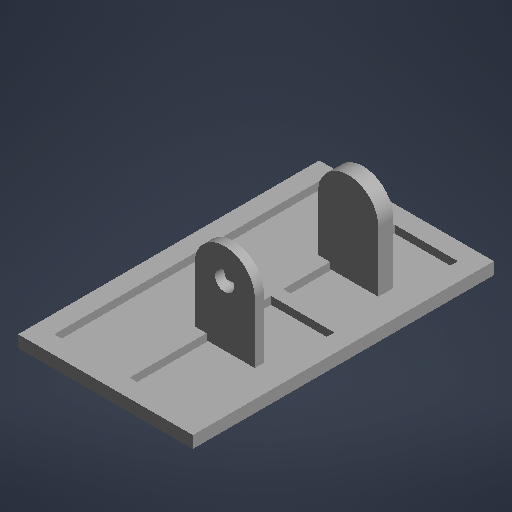
# Autodesk Inventor part: R2_pie_der
Saved by Autodesk Inventor 2027 (Build 310192060, 192F)
## iProperties
Part Number: R2_pie_der
Material: Genérico
Document SubType Name: Modelado
Designer: rodri
Appearance: Por defecto
Author: rodri
Autodesk Inventor part; units mm, degrees
ref_plane "Plano de trabajo1" through (0, 0, -45) normal (0, 0, 1) x (1, 0, 0)
sketch "Boceto1" plane through (0, 0, -45) normal (0, 0, 1) x (1, 0, 0)
  line L0 (-61, -166) -> (-3, -166)
  line L1 (-3, -166) -> (-3, -162)
  line L2 (-3, -162) -> (-61, -162)
  line L3 (-61, -162) -> (-61, -166)
  constraints: 8 end point, 2 parallel, 1 horizontal, 1 perpendicular
extrude "Extrusión1" add sketch "Boceto1" along normal blind 100
ref_plane "Plano de trabajo2" through (0, 0, -39) normal (0, 0, 1) x (1, 0, 0)
sketch "Boceto2" plane through (0, 0, -39) normal (0, 0, 1) x (1, 0, 0)
  line L0 (-55, -164.5) -> (-9, -164.5)
  line L1 (-9, -164.5) -> (-9, -161.9)
  line L2 (-9, -161.9) -> (-55, -161.9)
  line L3 (-55, -161.9) -> (-55, -164.5)
  constraints: 8 end point, 2 parallel, 1 horizontal, 1 perpendicular
extrude "Extrusión2" cut sketch "Boceto2" along normal blind 88
ref_plane "Plano de trabajo3" through (0, 0, -2) normal (0, 0, 1) x (1, 0, 0)
sketch "Boceto3" plane through (0, 0, -2) normal (0, 0, 1) x (1, 0, 0)
  line L0 (-55, -166) -> (-9, -166)
  line L1 (-9, -166) -> (-9, -162)
  line L2 (-9, -162) -> (-55, -162)
  line L3 (-55, -162) -> (-55, -166)
  constraints: 8 end point, 2 parallel, 1 horizontal, 1 perpendicular
extrude "Extrusión3" add sketch "Boceto3" along normal blind 4
ref_plane "Plano de trabajo4" through (0, 0, -39) normal (0, 0, 1) x (1, 0, 0)
sketch "Boceto4" plane through (0, 0, -39) normal (0, 0, 1) x (1, 0, 0)
  line L0 (-34, -166) -> (-30, -166)
  line L1 (-30, -166) -> (-30, -162)
  line L2 (-30, -162) -> (-34, -162)
  line L3 (-34, -162) -> (-34, -166)
  constraints: 8 end point, 2 parallel, 1 horizontal, 1 perpendicular
extrude "Extrusión4" add sketch "Boceto4" along normal blind 88
ref_plane "Plano de trabajo5" through (0, 0, -22.6) normal (0, 0, 1) x (1, 0, 0)
sketch "Boceto5" plane through (0, 0, -22.6) normal (0, 0, 1) x (1, 0, 0)
  line L0 (-34, -164) -> (-14, -164)
  line L1 (-14, -164) -> (-14, -144)
  line L2 (-14, -144) -> (-34, -144)
  line L3 (-34, -144) -> (-34, -164)
  constraints: 8 end point, 2 parallel, 1 horizontal, 1 perpendicular
extrude "Extrusión5" add sketch "Boceto5" along normal blind 4.99
ref_plane "Plano de trabajo6" through (0, 0, -22.6) normal (0, 0, 1) x (1, 0, 0)
sketch "Boceto6" plane through (0, 0, -22.6) normal (0, 0, 1) x (1, 0, 0)
  circle A0 centre (-24, -144) radius 10
  constraints: 1 centre point
extrude "Extrusión6" add sketch "Boceto6" along normal blind 4.99
ref_plane "Plano de trabajo7" through (0, 0, 20.41) normal (0, 0, 1) x (1, 0, 0)
sketch "Boceto7" plane through (0, 0, 20.41) normal (0, 0, 1) x (1, 0, 0)
  line L0 (-34, -164) -> (-14, -164)
  line L1 (-14, -164) -> (-14, -144)
  line L2 (-14, -144) -> (-34, -144)
  line L3 (-34, -144) -> (-34, -164)
  constraints: 8 end point, 2 parallel, 1 horizontal, 1 perpendicular
extrude "Extrusión7" add sketch "Boceto7" along normal blind 3
ref_plane "Plano de trabajo8" through (0, 0, 20.41) normal (0, 0, 1) x (1, 0, 0)
sketch "Boceto8" plane through (0, 0, 20.41) normal (0, 0, 1) x (1, 0, 0)
  circle A0 centre (-24, -144) radius 10
  constraints: 1 centre point
extrude "Extrusión8" add sketch "Boceto8" along normal blind 3
ref_plane "Plano de trabajo9" through (0, 0, -22.7) normal (0, 0, 1) x (1, 0, 0)
sketch "Boceto9" plane through (0, 0, -22.7) normal (0, 0, 1) x (1, 0, 0)
  circle A0 centre (-24, -144) radius 4.2
  constraints: 1 centre point
extrude "Extrusión9" cut sketch "Boceto9" along normal blind 3.2
ref_plane "Plano de trabajo10" through (0, 0, 20.3) normal (0, 0, 1) x (1, 0, 0)
sketch "Boceto10" plane through (0, 0, 20.3) normal (0, 0, 1) x (1, 0, 0)
  circle A0 centre (-24, -144) radius 3.15
  constraints: 1 centre point
extrude "Extrusión10" cut sketch "Boceto10" along normal blind 3.2
